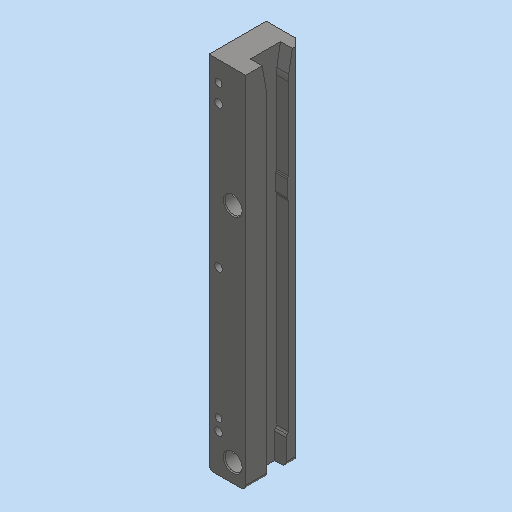
# Autodesk Inventor part: MM0948AN160_G01_163
Saved by Autodesk Inventor 2023.3 (Build 273359000, 359)
## iProperties
RuleStatus: InUse
Part Number: MM0948AN160_G01_163
Material: 1.2379 X155CrVMo12-1
Description: =<RBPARTNOTITLE2>
Document SubType Name: Modeling
Designer: ric7an
Mass: 2993.77 g
Surface Area: 621.276 cm^2
Volume: 381.372 cm^3
Density: 7.85 g/cm^3
Appearance: Stahl - rostfrei AnP
Created: 2023-03-23
BeforeDocSave0: file://AnP_Ansicht_ausrichten
RBDOCUMENTTYPE: DRF
RBDOCUMENTVERSION: 00
RBDRAWINGMAINSCALE: 1:1
RBDRAWINGMISSINGSPEC: --
RBDRAWINGVOLUME: --
RBGBEDGESIN1: +0,5
RBGBEDGESIN2: +0,2
RBGBEDGESOUT1: -0,3
RBGBEDGESOUT2: -0,1
RBMATERIAL: =<Material>
RBMATMEETS: --
RBMATNO: =<Part Number>
RBPARTMADEOF: 305 x 48,5 x 31 (FM)
RBPARTNO: SIEHE MNR
RBPARTNOTITLE1: manufactured part
RBPARTNOTITLE2: Anfertigungsteil
RBPARTSAFETYINDICATOR: --
RBSURFACE: vaccum hardened 58 HRC ± 1
RBSURFACE2: vakuumgehaertet 58 HRC ± 1
RBZEDGESNORM: ISO13715:2002-06
RBZGENDIMCLASS: m
RBZGENDIMNORM: ISO 2768-1:1989-11
RBZGENGEOCLASS: H
RBZGENGEONORM: ISO 2768-2:1989-11
RBZSURFACENORM: ISO13D2:2002-02
RBZTOLERANCENORM: ISO 14405-1:2010-12
AnP_Material: =<Material>
AnP_TemplVers: 20190222
AnP_Kategorie: 1
MaxAbmaße: 305 x 48,5 x 31 (FM)
d0: 48,500 mm
d1: 31,000 mm
d2: 10,000 mm
d3: 17,500 mm
d4: 18,500 mm
d5: 305,000 mm
d6: 0,00 grd
d8: 15,000 mm
d9: 0,500 mm
d12: 1,500 mm
d14: 0,00 grd
d15: 3,000 mm
d19: 15,000 mm
d24: 18,000 mm
d37: 6,600 mm
d39: 11,000 mm
d40: 6,800 mm
d52: 23,000 mm
d100: 20,000 mm
d102: 10,00 grd
d103: 20,000 mm
d105: 10,00 grd
d106: 30,000 mm
d110: 1,000 mm
d112: 30,00 grd
d113: 1,000 mm
d115: 30,00 grd
d133: 9,500 mm
d135: 10,000 mm
d139: 15,000 mm
d140: 118,00 grd
d141: 8,000 mm
d143: 10,000 mm
d147: 37,000 mm
d148: 118,00 grd
d149: 4,000 mm
d152: 8,000 mm
d153: 6,000 mm
d158: 12,000 mm
d160: 10,000 mm
d166: 8,000 mm
d167: 118,00 grd
d169: 15,000 mm
d171: 32,000 mm
d172: 32,000 mm
AnP_Kommentar_aktuell: =<Comments>
AnP_Material_aktuell: =<Material>
Author: FH/Wi
Keywords: =<RBPARTMADEOF>
Comments: =<RBSURFACE2>
Revision Number: 01
Autodesk Inventor part; units mm, degrees
ref_plane "YZ Plane" through (0, 0, 0) normal (1, 0, 0) x (0, 1, 0)
ref_plane "XZ Plane" through (0, 0, 0) normal (0, 1, 0) x (-1, 0, 0)
ref_plane "XY Plane" through (0, 0, 0) normal (0, 0, 1) x (1, 0, 0)
sketch "Skizze1" plane through (0, 0, 0) normal (0, 0, 1) x (1, 0, 0)
  line L0 (0, 0) -> (31, 0)
  line L1 (31, 0) -> (31, 48.5)
  line L2 (31, 48.5) -> (0, 48.5)
  line L3 (0, 48.5) -> (0, 0)
  line L4 (31, 17.5) -> (21, 17.5)
  line L5 (21, 17.5) -> (21, 36)
  line L6 (21, 36) -> (31, 36)
  line L7 (31, 36) -> (31, 17.5)
  dimension "d0" = 48.5
  dimension "d1" = 31
  dimension "d2" = 10
  dimension "d3" = 17.5
  dimension "d4" = 18.5
  constraints: 16 end point, 4 parallel, 2 horizontal, 2 perpendicular, 1 point on line
  measures "d0" distance of L2.end L0.start
  measures "d1" distance of L1.end L2.end
  measures "d2" distance of L5.end L6.end
  measures "d3" distance between parallel lines of L4 L0
  measures "d4" distance of L4.end L5.end
extrude "Extrusion1" add sketch "Skizze1" along normal mid plane 305 contours L3 L2 L1 L6 L5 L4 L0
sketch "Skizze2" plane through (31, 36, -152.5) normal (1, 0, 0) x (0, 0, -1)
  line L0 (-305, 0) -> (0, 0) projected
  line L1 (0, 12.5) -> (0, 0) projected
  line L2 (0, 12.5) -> (-305, 12.5) projected
  line L3 (-305, 0) -> (-305, 12.5) projected
  line L4 (-211.5, 0) -> (-196.5, 0)
  line L5 (-196.5, 0) -> (-196.5, -0.5)
  line L6 (-196.5, -0.5) -> (-211.5, -0.5)
  line L7 (-211.5, -0.5) -> (-211.5, 0)
  line L8 (0, 0) -> (-23, 0)
  line L9 (-23, 0) -> (-23, -1.5)
  line L10 (-23, -1.5) -> (0, -1.5)
  line L11 (0, -1.5) -> (0, 0)
  line L12 (0, 12.5) -> (0, 0) projected
  line L13 (0, 0) -> (0, -18.5) projected
  line L14 (-305, -18.5) -> (-305, 0) projected
  line L15 (0, -18.5) -> (-305, -18.5) projected
  point P0 (-152.5, -36)
  dimension "d8" = 15
  dimension "d9" = 0.5
  dimension "d12" = 1.5
  dimension "d52" = 23
  dimension "d173" = 108.5
  dimension "d180" = 18
  constraints: 16 end point, 4 parallel, 2 horizontal, 2 perpendicular, 2 point on line, 1 collinear
  measures "d8" distance of L5.end L6.end
  measures "d9" distance of L6.end L4.start
  measures "d12" distance of L8.end L9.end
  measures "d52" distance between parallel lines of L13 L9
  measures "d173" distance between parallel lines of L5 L14
  measures "d180" distance between parallel lines of L15 L6
extrude "Extrusion2" add sketch "Skizze2" against normal up to surface (10 mm away) contours L0 L5 L6 L7 | L0 L11 L10 L9
sketch "Skizze3" plane through (0, 0, 152.5) normal (0, -1, 0) x (1, 0, 0)
  line L0 (31, -305) -> (0, -305) projected
  line L1 (0, 0) -> (0, -305) projected
  line L2 (31, -305) -> (31, 0) projected
  line L3 (31, -282) -> (21, -282) projected
  line L4 (21, -305) -> (21, -282) projected
  line L5 (21, -108.5) -> (21, -93.5) projected
  point P0 (0, -152.5)
  point P1 (20, -101)
  point P2 (20, -289.5)
  dimension "d176" = 11
  dimension "d177" = 7.5
  dimension "d178" = 7.5
  constraints: 1 vertical alignment
  measures "d176" distance from line of L2 point (20, -289.5)
  measures "d177" vertical distance of point (20, -101) L5.end
  measures "d178" distance from line of point (20, -289.5) L3
hole "Bohrung1" at (20, 0, 51.5) at (20, 0, -137) direction (0, 1, 0) diameter 15 depth 18
fillet "Rundung1" radius 3 6 edges at (26, 36, 59) (26, 35.5, 59) (26, 35.5, 44) (26, 36, 44) (26, 36, -129.5) (26, 34.5, -129.5)
sketch "Skizze5" plane through (0, 48.5, 152.5) normal (0, 1, 0) x (1, 0, 0)
  line L0 (0, 305) -> (0, 0) projected
  line L1 (0, 305) -> (31, 305) projected
  line L2 (31, 0) -> (0, 0) projected
  point P0 (0, 152.5)
  point P1 (8, 32)
  point P2 (8, 152.5)
  point P3 (8, 273)
  point P4 (0, 152.5)
  point P5 (0, 152.5)
  dimension "d171" = 32
  dimension "d172" = 32
  dimension "d179" = 8
  constraints: 2 midpoint, 2 vertical alignment, 1 horizontal alignment
  measures "d171" distance from line of L2 point (8, 32)
  measures "d172" distance from line of point (8, 273) L1
  measures "d179" distance from line of point (8, 273) L0
hole "Bohrung3" at (8, 48.5, 120.5) at (8, 48.5, 0) at (8, 48.5, -120.5) direction (0, -1, 0) diameter 6.6 end through all counterbore diameter 11 counterbore depth 6.8 clearance for "Inbusschraube ISO 4762  versenkt" size "M6" standard "ISO"
chamfer "Fase1" distance 20 angle 10 1 edges at (26, 17.5, 152.5) measured on face at (26, 17.5, 152)
chamfer "Fase2" distance 20 angle 10 1 edges at (26, 36, 152.5) measured on face at (26, 36, 152)
fillet "Rundung2" radius 30 2 edges at (26, 17.5, 132.5) (26, 36, 132.5)
chamfer "Fase3" distance 1 angle 30 1 edges at (20, 0, 59) measured on face at (20, 0.5, 59)
chamfer "Fase4" distance 1 angle 30 1 edges at (20, 0, -129.5) measured on face at (20, 0.5, -129.5)
sketch "Skizze13" plane through (0, 0, 152.5) normal (-1, 0, 0) x (0, 0, 1)
  line L0 (0, 0) -> (-305, 0) projected
  line L1 (-282, 1) -> (-297, 1) projected
  line L2 (-93.5, 1) -> (-108.5, 1) projected
  point P0 (-152.5, 0)
  point P1 (-289.5, 9.5)
  point P2 (-101, 9.5)
  point P3 (-289.5, 1)
  point P4 (-101, 1)
  dimension "d133" = 9.5
  constraints: 2 midpoint, 2 vertical alignment, 1 horizontal alignment
  measures "d133" distance from line of L0 point (-289.5, 9.5)
hole "Bohrung11" at (0, 9.5, -137) at (0, 9.5, 51.5) direction (1, 0, 0) diameter 4.134 depth 15 tip angle 118 thread size "M5x0.8" designation "M5" class "6H" standard "ISO Metric profile"
sketch "Skizze14" plane through (0, 48.5, 152.5) normal (0, 1, 0) x (1, 0, 0)
  line L0 (0, 98.933) -> (0, 103.067) projected
  line L1 (0, 287.433) -> (0, 291.567) projected
  line L2 (21, 110.1583) -> (21, 279.4019) projected
  line L3 (21, 305) -> (21, 283.3706) projected
  arc A0 (21, 296.933) -> (21, 282.067) centre (20, 289.5) ccw projected
  arc A1 (21, 108.433) -> (21, 93.567) centre (20, 101) ccw projected
  line L4 (0, 305) -> (0, 0) projected
  point P0 (0, 152.5)
  point P1 (8, 289.5)
  point P2 (8, 101)
  point P3 (0, 289.5)
  point P4 (0, 101)
  point P5 (21, 67)
  point P6 (21, 249)
  dimension "d141" = 8
  constraints: 2 horizontal alignment, 2 midpoint, 1 vertical alignment, 1 other
hole "Bohrung12" at (8, 48.5, -137) at (8, 48.5, 51.5) direction (0, -1, 0) diameter 4.134 depth 37 tip angle 118 thread size "M5x0.8" designation "M5" class "6H" standard "ISO Metric profile"
chamfer "Fase6" distance 6 angle 45 1 edges at (31, 48.5, 0)
fillet "Rundung4" radius 4 3 edges at (0, 24.25, -152.5) (31, 8.75, -152.5) (31, 38.5, -152.5)
sketch "Skizze15" plane through (0, 0, 152.5) normal (0, -1, 0) x (1, 0, 0)
  line L0 (-6.2, -152.5) -> (37.2, -152.5) projected
  line L1 (0, 0) -> (0, -301) projected
  circle A0 centre (8, -32) radius 3.3 projected
  circle A1 centre (8, -273) radius 3.3 projected
  point P0 (0, -152.5)
  point P1 (8, -17)
  point P2 (8, -263)
  dimension "d152" = 8
  dimension "d169" = 15
  dimension "d191" = 10
  constraints: 1 vertical alignment
  measures "d152" distance from line of point (8, -263) L1
  measures "d169" distance of A0.centre point (8, -17)
  measures "d191" distance of A1.centre point (8, -263)
hole "Bohrung13" at (8, 0, 135.5) at (8, 0, -110.5) direction (0, 1, 0) diameter 6 depth 12 tip angle 118
sketch "Skizze17" plane through (0, 0, 152.5) normal (-1, 0, 0) x (0, 0, 1)
  line L0 (-291.567, 48.5) -> (-287.433, 48.5) projected
  line L1 (-103.067, 48.5) -> (-98.933, 48.5) projected
  circle A0 centre (-289.5, 9.5) radius 2.067 projected
  circle A1 centre (-101, 9.5) radius 2.067 projected
  line L2 (-301, 48.5) -> (0, 48.5) projected
  point P0 (-152.5, 0)
  point P1 (-289.5, 38.5)
  point P2 (-101, 38.5)
  dimension "d160" = 10
  constraints: 2 vertical alignment, 1 horizontal alignment
  measures "d160" distance from line of L2 point (-289.5, 38.5)
hole "Bohrung14" at (0, 38.5, -137) at (0, 38.5, 51.5) direction (1, 0, 0) diameter 4.134 depth 8 tip angle 118 thread size "M5x0.8" designation "M5" class "6H" standard "ISO Metric profile"
